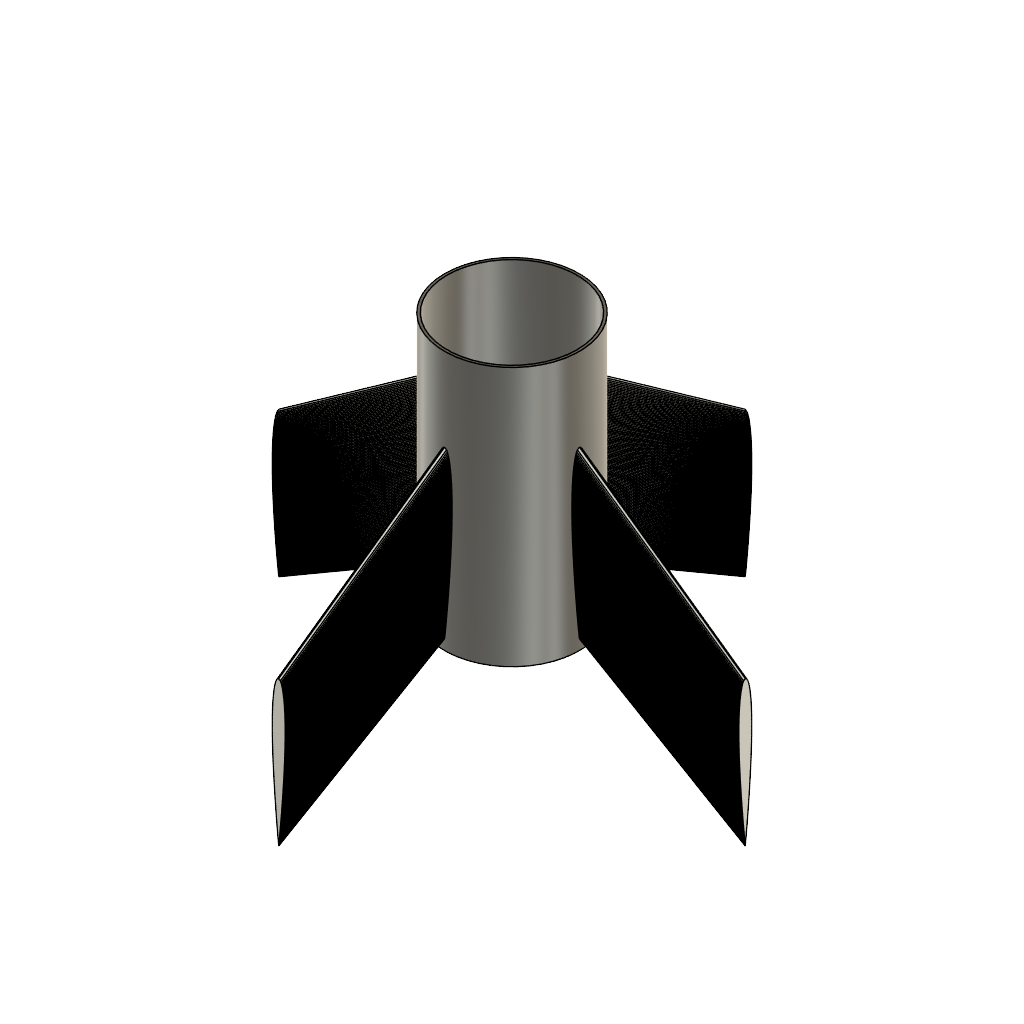
Finh canh (Autodesk Fusion 360 design; units mm, degrees)
part number: 2026-10-23-18-15-36-420
Autodesk Fusion 360 part; units mm, degrees
other "Base Mesh Feature1"
sketch "Sketch7" plane through (0, 0, 0) normal (0, 0, 1) x (1, 0, 0)
other "Modify1"
other "Modify2"
other "Modify3"
sketch "Sketch9" plane through (0, 0, 0) normal (0, 0, 1) x (1, 0, 0)
sketch "Sketch10" plane through (0, 0, 0) normal (0, 0, 1) x (1, 0, 0)
  circle A0 centre (0, 0) radius 65
  circle A1 centre (0, 0) radius 62.5
  dimension "d106" = 130
  dimension "d107" = 125
  constraint coincident A0.centre A1.centre
  measures "d106" diameter of A0
  measures "d107" diameter of A1
extrude "Extrude18" add sketch "Sketch10" along normal blind 250 makes body 1
sketch "Sketch11" plane through (0, 0, 0) normal (0, 0, 1) x (1, 0, 0)
  line L0 (0, 0) -> (140, 0) construction
  dimension "d110" = 140
  constraint coincident L0.start origin
  constraint horizontal L0
  measures "d110" distance of L0.start L0.end
sketch "Airfoil NACA 0009" plane through (0, 0, 0) normal (0, 0, 1) x (1, 0, 0)
  line L0 (140, 0) -> (138.8333, 0.1265)
  line L1 (138.8333, 0.1265) -> (137.6667, 0.2516)
  line L2 (137.6667, 0.2516) -> (136.5, 0.3755)
  line L3 (136.5, 0.3755) -> (135.3333, 0.498)
  line L4 (135.3333, 0.498) -> (134.1667, 0.6192)
  line L5 (134.1667, 0.6192) -> (133, 0.7391)
  line L6 (133, 0.7391) -> (131.8333, 0.8578)
  line L7 (131.8333, 0.8578) -> (130.6667, 0.9753)
  line L8 (130.6667, 0.9753) -> (129.5, 1.0916)
  line L9 (129.5, 1.0916) -> (128.3333, 1.2067)
  line L10 (128.3333, 1.2067) -> (127.1667, 1.3206)
  line L11 (127.1667, 1.3206) -> (126, 1.4333)
  line L12 (126, 1.4333) -> (124.8333, 1.5449)
  line L13 (124.8333, 1.5449) -> (123.6667, 1.6554)
  line L14 (123.6667, 1.6554) -> (122.5, 1.7647)
  line L15 (122.5, 1.7647) -> (121.3333, 1.8729)
  line L16 (121.3333, 1.8729) -> (120.1667, 1.9801)
  line L17 (120.1667, 1.9801) -> (119, 2.0861)
  line L18 (119, 2.0861) -> (117.8333, 2.1911)
  line L19 (117.8333, 2.1911) -> (116.6667, 2.295)
  line L20 (116.6667, 2.295) -> (115.5, 2.3979)
  line L21 (115.5, 2.3979) -> (114.3333, 2.4996)
  line L22 (114.3333, 2.4996) -> (113.1667, 2.6004)
  line L23 (113.1667, 2.6004) -> (112, 2.7001)
  line L24 (112, 2.7001) -> (110.8333, 2.7987)
  line L25 (110.8333, 2.7987) -> (109.6667, 2.8964)
  line L26 (109.6667, 2.8964) -> (108.5, 2.9929)
  line L27 (108.5, 2.9929) -> (107.3333, 3.0885)
  line L28 (107.3333, 3.0885) -> (106.1667, 3.183)
  line L29 (106.1667, 3.183) -> (105, 3.2765)
  line L30 (105, 3.2765) -> (103.8333, 3.3689)
  line L31 (103.8333, 3.3689) -> (102.6667, 3.4603)
  line L32 (102.6667, 3.4603) -> (101.5, 3.5506)
  line L33 (101.5, 3.5506) -> (100.3333, 3.6399)
  line L34 (100.3333, 3.6399) -> (99.1667, 3.7282)
  line L35 (99.1667, 3.7282) -> (98, 3.8153)
  line L36 (98, 3.8153) -> (96.8333, 3.9014)
  line L37 (96.8333, 3.9014) -> (95.6667, 3.9865)
  line L38 (95.6667, 3.9865) -> (94.5, 4.0704)
  line L39 (94.5, 4.0704) -> (93.3333, 4.1532)
  line L40 (93.3333, 4.1532) -> (92.1667, 4.2349)
  line L41 (92.1667, 4.2349) -> (91, 4.3155)
  line L42 (91, 4.3155) -> (89.8333, 4.3949)
  line L43 (89.8333, 4.3949) -> (88.6667, 4.4732)
  line L44 (88.6667, 4.4732) -> (87.5, 4.5503)
  line L45 (87.5, 4.5503) -> (86.3333, 4.6262)
  line L46 (86.3333, 4.6262) -> (85.1667, 4.7009)
  line L47 (85.1667, 4.7009) -> (84, 4.7744)
  line L48 (84, 4.7744) -> (82.8333, 4.8466)
  line L49 (82.8333, 4.8466) -> (81.6667, 4.9175)
  line L50 (81.6667, 4.9175) -> (80.5, 4.9871)
  line L51 (80.5, 4.9871) -> (79.3333, 5.0554)
  line L52 (79.3333, 5.0554) -> (78.1667, 5.1224)
  line L53 (78.1667, 5.1224) -> (77, 5.1879)
  line L54 (77, 5.1879) -> (75.8333, 5.2521)
  line L55 (75.8333, 5.2521) -> (74.6667, 5.3148)
  line L56 (74.6667, 5.3148) -> (73.5, 5.376)
  line L57 (73.5, 5.376) -> (72.3333, 5.4357)
  line L58 (72.3333, 5.4357) -> (71.1667, 5.4939)
  line L59 (71.1667, 5.4939) -> (70, 5.5505)
  line L60 (70, 5.5505) -> (68.8333, 5.6054)
  line L61 (68.8333, 5.6054) -> (67.6667, 5.6587)
  line L62 (67.6667, 5.6587) -> (66.5, 5.7103)
  line L63 (66.5, 5.7103) -> (65.3333, 5.7601)
  line L64 (65.3333, 5.7601) -> (64.1667, 5.8082)
  line L65 (64.1667, 5.8082) -> (63, 5.8543)
  line L66 (63, 5.8543) -> (61.8333, 5.8986)
  line L67 (61.8333, 5.8986) -> (60.6667, 5.941)
  line L68 (60.6667, 5.941) -> (59.5, 5.9813)
  line L69 (59.5, 5.9813) -> (58.3333, 6.0196)
  line L70 (58.3333, 6.0196) -> (57.1667, 6.0558)
  line L71 (57.1667, 6.0558) -> (56, 6.0898)
  line L72 (56, 6.0898) -> (54.8333, 6.1215)
  line L73 (54.8333, 6.1215) -> (53.6667, 6.1509)
  line L74 (53.6667, 6.1509) -> (52.5, 6.178)
  line L75 (52.5, 6.178) -> (51.3333, 6.2026)
  line L76 (51.3333, 6.2026) -> (50.1667, 6.2246)
  line L77 (50.1667, 6.2246) -> (49, 6.2441)
  line L78 (49, 6.2441) -> (47.8333, 6.2608)
  line L79 (47.8333, 6.2608) -> (46.6667, 6.2748)
  line L80 (46.6667, 6.2748) -> (45.5, 6.2858)
  line L81 (45.5, 6.2858) -> (44.3333, 6.2939)
  line L82 (44.3333, 6.2939) -> (43.1667, 6.2989)
  line L83 (43.1667, 6.2989) -> (42, 6.3007)
  line L84 (42, 6.3007) -> (40.8333, 6.2993)
  line L85 (40.8333, 6.2993) -> (39.6667, 6.2943)
  line L86 (39.6667, 6.2943) -> (38.5, 6.2859)
  line L87 (38.5, 6.2859) -> (37.3333, 6.2737)
  line L88 (37.3333, 6.2737) -> (36.1667, 6.2578)
  line L89 (36.1667, 6.2578) -> (35, 6.2378)
  line L90 (35, 6.2378) -> (33.8333, 6.2137)
  line L91 (33.8333, 6.2137) -> (32.6667, 6.1852)
  line L92 (32.6667, 6.1852) -> (31.5, 6.1523)
  line L93 (31.5, 6.1523) -> (30.3333, 6.1146)
  line L94 (30.3333, 6.1146) -> (29.1667, 6.072)
  line L95 (29.1667, 6.072) -> (28, 6.0242)
  line L96 (28, 6.0242) -> (26.8333, 5.971)
  line L97 (26.8333, 5.971) -> (25.6667, 5.9121)
  line L98 (25.6667, 5.9121) -> (24.5, 5.8471)
  line L99 (24.5, 5.8471) -> (23.3333, 5.7757)
  line L100 (23.3333, 5.7757) -> (22.1667, 5.6976)
  line L101 (22.1667, 5.6976) -> (21, 5.6124)
  line L102 (21, 5.6124) -> (19.8333, 5.5194)
  line L103 (19.8333, 5.5194) -> (18.6667, 5.4182)
  line L104 (18.6667, 5.4182) -> (17.5, 5.3081)
  line L105 (17.5, 5.3081) -> (16.3333, 5.1885)
  line L106 (16.3333, 5.1885) -> (15.1667, 5.0584)
  line L107 (15.1667, 5.0584) -> (14, 4.9169)
  line L108 (14, 4.9169) -> (12.8333, 4.7627)
  line L109 (12.8333, 4.7627) -> (11.6667, 4.5943)
  line L110 (11.6667, 4.5943) -> (10.5, 4.4099)
  line L111 (10.5, 4.4099) -> (9.3333, 4.2071)
  line L112 (9.3333, 4.2071) -> (8.1667, 3.9827)
  line L113 (8.1667, 3.9827) -> (7, 3.7324)
  line L114 (7, 3.7324) -> (5.8333, 3.4502)
  line L115 (5.8333, 3.4502) -> (4.6667, 3.1264)
  line L116 (4.6667, 3.1264) -> (3.5, 2.7455)
  line L117 (3.5, 2.7455) -> (2.3333, 2.2764)
  line L118 (2.3333, 2.2764) -> (1.1667, 1.6398)
  line L119 (1.1667, 1.6398) -> (0, 0)
  line L120 (0, 0) -> (1.1667, -1.6398)
  line L121 (1.1667, -1.6398) -> (2.3333, -2.2764)
  line L122 (2.3333, -2.2764) -> (3.5, -2.7455)
  line L123 (3.5, -2.7455) -> (4.6667, -3.1264)
  line L124 (4.6667, -3.1264) -> (5.8333, -3.4502)
  line L125 (5.8333, -3.4502) -> (7, -3.7324)
  line L126 (7, -3.7324) -> (8.1667, -3.9827)
  line L127 (8.1667, -3.9827) -> (9.3333, -4.2071)
  line L128 (9.3333, -4.2071) -> (10.5, -4.4099)
  line L129 (10.5, -4.4099) -> (11.6667, -4.5943)
  line L130 (11.6667, -4.5943) -> (12.8333, -4.7627)
  line L131 (12.8333, -4.7627) -> (14, -4.9169)
  line L132 (14, -4.9169) -> (15.1667, -5.0584)
  line L133 (15.1667, -5.0584) -> (16.3333, -5.1885)
  line L134 (16.3333, -5.1885) -> (17.5, -5.3081)
  line L135 (17.5, -5.3081) -> (18.6667, -5.4182)
  line L136 (18.6667, -5.4182) -> (19.8333, -5.5194)
  line L137 (19.8333, -5.5194) -> (21, -5.6124)
  line L138 (21, -5.6124) -> (22.1667, -5.6976)
  line L139 (22.1667, -5.6976) -> (23.3333, -5.7757)
  line L140 (23.3333, -5.7757) -> (24.5, -5.8471)
  line L141 (24.5, -5.8471) -> (25.6667, -5.9121)
  line L142 (25.6667, -5.9121) -> (26.8333, -5.971)
  line L143 (26.8333, -5.971) -> (28, -6.0242)
  line L144 (28, -6.0242) -> (29.1667, -6.072)
  line L145 (29.1667, -6.072) -> (30.3333, -6.1146)
  line L146 (30.3333, -6.1146) -> (31.5, -6.1523)
  line L147 (31.5, -6.1523) -> (32.6667, -6.1852)
  line L148 (32.6667, -6.1852) -> (33.8333, -6.2137)
  line L149 (33.8333, -6.2137) -> (35, -6.2378)
  line L150 (35, -6.2378) -> (36.1667, -6.2578)
  line L151 (36.1667, -6.2578) -> (37.3333, -6.2737)
  line L152 (37.3333, -6.2737) -> (38.5, -6.2859)
  line L153 (38.5, -6.2859) -> (39.6667, -6.2943)
  line L154 (39.6667, -6.2943) -> (40.8333, -6.2993)
  line L155 (40.8333, -6.2993) -> (42, -6.3007)
  line L156 (42, -6.3007) -> (43.1667, -6.2989)
  line L157 (43.1667, -6.2989) -> (44.3333, -6.2939)
  line L158 (44.3333, -6.2939) -> (45.5, -6.2858)
  line L159 (45.5, -6.2858) -> (46.6667, -6.2748)
  line L160 (46.6667, -6.2748) -> (47.8333, -6.2608)
  line L161 (47.8333, -6.2608) -> (49, -6.2441)
  line L162 (49, -6.2441) -> (50.1667, -6.2246)
  line L163 (50.1667, -6.2246) -> (51.3333, -6.2026)
  line L164 (51.3333, -6.2026) -> (52.5, -6.178)
  line L165 (52.5, -6.178) -> (53.6667, -6.1509)
  line L166 (53.6667, -6.1509) -> (54.8333, -6.1215)
  line L167 (54.8333, -6.1215) -> (56, -6.0898)
  line L168 (56, -6.0898) -> (57.1667, -6.0558)
  line L169 (57.1667, -6.0558) -> (58.3333, -6.0196)
  line L170 (58.3333, -6.0196) -> (59.5, -5.9813)
  line L171 (59.5, -5.9813) -> (60.6667, -5.941)
  line L172 (60.6667, -5.941) -> (61.8333, -5.8986)
  line L173 (61.8333, -5.8986) -> (63, -5.8543)
  line L174 (63, -5.8543) -> (64.1667, -5.8082)
  line L175 (64.1667, -5.8082) -> (65.3333, -5.7601)
  line L176 (65.3333, -5.7601) -> (66.5, -5.7103)
  line L177 (66.5, -5.7103) -> (67.6667, -5.6587)
  line L178 (67.6667, -5.6587) -> (68.8333, -5.6054)
  line L179 (68.8333, -5.6054) -> (70, -5.5505)
  line L180 (70, -5.5505) -> (71.1667, -5.4939)
  line L181 (71.1667, -5.4939) -> (72.3333, -5.4357)
  line L182 (72.3333, -5.4357) -> (73.5, -5.376)
  line L183 (73.5, -5.376) -> (74.6667, -5.3148)
  line L184 (74.6667, -5.3148) -> (75.8333, -5.2521)
  line L185 (75.8333, -5.2521) -> (77, -5.1879)
  line L186 (77, -5.1879) -> (78.1667, -5.1224)
  line L187 (78.1667, -5.1224) -> (79.3333, -5.0554)
  line L188 (79.3333, -5.0554) -> (80.5, -4.9871)
  line L189 (80.5, -4.9871) -> (81.6667, -4.9175)
  line L190 (81.6667, -4.9175) -> (82.8333, -4.8466)
  line L191 (82.8333, -4.8466) -> (84, -4.7744)
  line L192 (84, -4.7744) -> (85.1667, -4.7009)
  line L193 (85.1667, -4.7009) -> (86.3333, -4.6262)
  line L194 (86.3333, -4.6262) -> (87.5, -4.5503)
  line L195 (87.5, -4.5503) -> (88.6667, -4.4732)
  line L196 (88.6667, -4.4732) -> (89.8333, -4.3949)
  line L197 (89.8333, -4.3949) -> (91, -4.3155)
  line L198 (91, -4.3155) -> (92.1667, -4.2349)
  line L199 (92.1667, -4.2349) -> (93.3333, -4.1532)
  line L200 (93.3333, -4.1532) -> (94.5, -4.0704)
  line L201 (94.5, -4.0704) -> (95.6667, -3.9865)
  line L202 (95.6667, -3.9865) -> (96.8333, -3.9014)
  line L203 (96.8333, -3.9014) -> (98, -3.8153)
  line L204 (98, -3.8153) -> (99.1667, -3.7282)
  line L205 (99.1667, -3.7282) -> (100.3333, -3.6399)
  line L206 (100.3333, -3.6399) -> (101.5, -3.5506)
  line L207 (101.5, -3.5506) -> (102.6667, -3.4603)
  line L208 (102.6667, -3.4603) -> (103.8333, -3.3689)
  line L209 (103.8333, -3.3689) -> (105, -3.2765)
  line L210 (105, -3.2765) -> (106.1667, -3.183)
  line L211 (106.1667, -3.183) -> (107.3333, -3.0885)
  line L212 (107.3333, -3.0885) -> (108.5, -2.9929)
  line L213 (108.5, -2.9929) -> (109.6667, -2.8964)
  line L214 (109.6667, -2.8964) -> (110.8333, -2.7987)
  line L215 (110.8333, -2.7987) -> (112, -2.7001)
  line L216 (112, -2.7001) -> (113.1667, -2.6004)
  line L217 (113.1667, -2.6004) -> (114.3333, -2.4996)
  line L218 (114.3333, -2.4996) -> (115.5, -2.3979)
  line L219 (115.5, -2.3979) -> (116.6667, -2.295)
  line L220 (116.6667, -2.295) -> (117.8333, -2.1911)
  line L221 (117.8333, -2.1911) -> (119, -2.0861)
  line L222 (119, -2.0861) -> (120.1667, -1.9801)
  line L223 (120.1667, -1.9801) -> (121.3333, -1.8729)
  line L224 (121.3333, -1.8729) -> (122.5, -1.7647)
  line L225 (122.5, -1.7647) -> (123.6667, -1.6554)
  line L226 (123.6667, -1.6554) -> (124.8333, -1.5449)
  line L227 (124.8333, -1.5449) -> (126, -1.4333)
  line L228 (126, -1.4333) -> (127.1667, -1.3206)
  line L229 (127.1667, -1.3206) -> (128.3333, -1.2067)
  line L230 (128.3333, -1.2067) -> (129.5, -1.0916)
  line L231 (129.5, -1.0916) -> (130.6667, -0.9753)
  line L232 (130.6667, -0.9753) -> (131.8333, -0.8578)
  line L233 (131.8333, -0.8578) -> (133, -0.7391)
  line L234 (133, -0.7391) -> (134.1667, -0.6192)
  line L235 (134.1667, -0.6192) -> (135.3333, -0.498)
  line L236 (135.3333, -0.498) -> (136.5, -0.3755)
  line L237 (136.5, -0.3755) -> (137.6667, -0.2516)
  line L238 (137.6667, -0.2516) -> (138.8333, -0.1265)
  line L239 (138.8333, -0.1265) -> (140, 0)
  line L240 (140, 0) -> (140, 0)
scale "Scale1" [no effect]
ref_plane "WorkPlane3" through (70, 0, 160) normal (0, 0, 1) x (1, 0, 0)
sketch "Airfoil NACA 0009 (1)" plane through (0, 0, 160) normal (0, 0, 1) x (1, 0, 0)
  line L0 (46.72, 0) -> (45.3867, 0.1446)
  line L1 (45.3867, 0.1446) -> (44.0533, 0.2876)
  line L2 (44.0533, 0.2876) -> (42.72, 0.4291)
  line L3 (42.72, 0.4291) -> (41.3867, 0.5691)
  line L4 (41.3867, 0.5691) -> (40.0533, 0.7076)
  line L5 (40.0533, 0.7076) -> (38.72, 0.8447)
  line L6 (38.72, 0.8447) -> (37.3867, 0.9804)
  line L7 (37.3867, 0.9804) -> (36.0533, 1.1146)
  line L8 (36.0533, 1.1146) -> (34.72, 1.2475)
  line L9 (34.72, 1.2475) -> (33.3867, 1.379)
  line L10 (33.3867, 1.379) -> (32.0533, 1.5092)
  line L11 (32.0533, 1.5092) -> (30.72, 1.6381)
  line L12 (30.72, 1.6381) -> (29.3867, 1.7656)
  line L13 (29.3867, 1.7656) -> (28.0533, 1.8918)
  line L14 (28.0533, 1.8918) -> (26.72, 2.0168)
  line L15 (26.72, 2.0168) -> (25.3867, 2.1405)
  line L16 (25.3867, 2.1405) -> (24.0533, 2.2629)
  line L17 (24.0533, 2.2629) -> (22.72, 2.3841)
  line L18 (22.72, 2.3841) -> (21.3867, 2.5041)
  line L19 (21.3867, 2.5041) -> (20.0533, 2.6229)
  line L20 (20.0533, 2.6229) -> (18.72, 2.7404)
  line L21 (18.72, 2.7404) -> (17.3867, 2.8567)
  line L22 (17.3867, 2.8567) -> (16.0533, 2.9719)
  line L23 (16.0533, 2.9719) -> (14.72, 3.0858)
  line L24 (14.72, 3.0858) -> (13.3867, 3.1986)
  line L25 (13.3867, 3.1986) -> (12.0533, 3.3101)
  line L26 (12.0533, 3.3101) -> (10.72, 3.4205)
  line L27 (10.72, 3.4205) -> (9.3867, 3.5297)
  line L28 (9.3867, 3.5297) -> (8.0533, 3.6377)
  line L29 (8.0533, 3.6377) -> (6.72, 3.7445)
  line L30 (6.72, 3.7445) -> (5.3867, 3.8502)
  line L31 (5.3867, 3.8502) -> (4.0533, 3.9546)
  line L32 (4.0533, 3.9546) -> (2.72, 4.0579)
  line L33 (2.72, 4.0579) -> (1.3867, 4.1599)
  line L34 (1.3867, 4.1599) -> (0.0533, 4.2608)
  line L35 (0.0533, 4.2608) -> (-1.28, 4.3604)
  line L36 (-1.28, 4.3604) -> (-2.6133, 4.4588)
  line L37 (-2.6133, 4.4588) -> (-3.9467, 4.556)
  line L38 (-3.9467, 4.556) -> (-5.28, 4.6519)
  line L39 (-5.28, 4.6519) -> (-6.6133, 4.7465)
  line L40 (-6.6133, 4.7465) -> (-7.9467, 4.8399)
  line L41 (-7.9467, 4.8399) -> (-9.28, 4.932)
  line L42 (-9.28, 4.932) -> (-10.6133, 5.0228)
  line L43 (-10.6133, 5.0228) -> (-11.9467, 5.1123)
  line L44 (-11.9467, 5.1123) -> (-13.28, 5.2004)
  line L45 (-13.28, 5.2004) -> (-14.6133, 5.2871)
  line L46 (-14.6133, 5.2871) -> (-15.9467, 5.3725)
  line L47 (-15.9467, 5.3725) -> (-17.28, 5.4564)
  line L48 (-17.28, 5.4564) -> (-18.6133, 5.539)
  line L49 (-18.6133, 5.539) -> (-19.9467, 5.62)
  line L50 (-19.9467, 5.62) -> (-21.28, 5.6996)
  line L51 (-21.28, 5.6996) -> (-22.6133, 5.7777)
  line L52 (-22.6133, 5.7777) -> (-23.9467, 5.8542)
  line L53 (-23.9467, 5.8542) -> (-25.28, 5.9291)
  line L54 (-25.28, 5.9291) -> (-26.6133, 6.0024)
  line L55 (-26.6133, 6.0024) -> (-27.9467, 6.074)
  line L56 (-27.9467, 6.074) -> (-29.28, 6.144)
  line L57 (-29.28, 6.144) -> (-30.6133, 6.2122)
  line L58 (-30.6133, 6.2122) -> (-31.9467, 6.2787)
  line L59 (-31.9467, 6.2787) -> (-33.28, 6.3434)
  line L60 (-33.28, 6.3434) -> (-34.6133, 6.4062)
  line L61 (-34.6133, 6.4062) -> (-35.9467, 6.4671)
  line L62 (-35.9467, 6.4671) -> (-37.28, 6.526)
  line L63 (-37.28, 6.526) -> (-38.6133, 6.583)
  line L64 (-38.6133, 6.583) -> (-39.9467, 6.6379)
  line L65 (-39.9467, 6.6379) -> (-41.28, 6.6907)
  line L66 (-41.28, 6.6907) -> (-42.6133, 6.7413)
  line L67 (-42.6133, 6.7413) -> (-43.9467, 6.7897)
  line L68 (-43.9467, 6.7897) -> (-45.28, 6.8358)
  line L69 (-45.28, 6.8358) -> (-46.6133, 6.8796)
  line L70 (-46.6133, 6.8796) -> (-47.9467, 6.9209)
  line L71 (-47.9467, 6.9209) -> (-49.28, 6.9597)
  line L72 (-49.28, 6.9597) -> (-50.6133, 6.996)
  line L73 (-50.6133, 6.996) -> (-51.9467, 7.0296)
  line L74 (-51.9467, 7.0296) -> (-53.28, 7.0606)
  line L75 (-53.28, 7.0606) -> (-54.6133, 7.0887)
  line L76 (-54.6133, 7.0887) -> (-55.9467, 7.1139)
  line L77 (-55.9467, 7.1139) -> (-57.28, 7.1361)
  line L78 (-57.28, 7.1361) -> (-58.6133, 7.1552)
  line L79 (-58.6133, 7.1552) -> (-59.9467, 7.1711)
  line L80 (-59.9467, 7.1711) -> (-61.28, 7.1838)
  line L81 (-61.28, 7.1838) -> (-62.6133, 7.193)
  line L82 (-62.6133, 7.193) -> (-63.9467, 7.1988)
  line L83 (-63.9467, 7.1988) -> (-65.28, 7.2008)
  line L84 (-65.28, 7.2008) -> (-66.6133, 7.1992)
  line L85 (-66.6133, 7.1992) -> (-67.9467, 7.1935)
  line L86 (-67.9467, 7.1935) -> (-69.28, 7.1839)
  line L87 (-69.28, 7.1839) -> (-70.6133, 7.17)
  line L88 (-70.6133, 7.17) -> (-71.9467, 7.1517)
  line L89 (-71.9467, 7.1517) -> (-73.28, 7.1289)
  line L90 (-73.28, 7.1289) -> (-74.6133, 7.1013)
  line L91 (-74.6133, 7.1013) -> (-75.9467, 7.0688)
  line L92 (-75.9467, 7.0688) -> (-77.28, 7.0312)
  line L93 (-77.28, 7.0312) -> (-78.6133, 6.9881)
  line L94 (-78.6133, 6.9881) -> (-79.9467, 6.9394)
  line L95 (-79.9467, 6.9394) -> (-81.28, 6.8848)
  line L96 (-81.28, 6.8848) -> (-82.6133, 6.824)
  line L97 (-82.6133, 6.824) -> (-83.9467, 6.7566)
  line L98 (-83.9467, 6.7566) -> (-85.28, 6.6824)
  line L99 (-85.28, 6.6824) -> (-86.6133, 6.6009)
  line L100 (-86.6133, 6.6009) -> (-87.9467, 6.5116)
  line L101 (-87.9467, 6.5116) -> (-89.28, 6.4141)
  line L102 (-89.28, 6.4141) -> (-90.6133, 6.3079)
  line L103 (-90.6133, 6.3079) -> (-91.9467, 6.1922)
  line L104 (-91.9467, 6.1922) -> (-93.28, 6.0664)
  line L105 (-93.28, 6.0664) -> (-94.6133, 5.9297)
  line L106 (-94.6133, 5.9297) -> (-95.9467, 5.7811)
  line L107 (-95.9467, 5.7811) -> (-97.28, 5.6193)
  line L108 (-97.28, 5.6193) -> (-98.6133, 5.4431)
  line L109 (-98.6133, 5.4431) -> (-99.9467, 5.2506)
  line L110 (-99.9467, 5.2506) -> (-101.28, 5.0399)
  line L111 (-101.28, 5.0399) -> (-102.6133, 4.8081)
  line L112 (-102.6133, 4.8081) -> (-103.9467, 4.5516)
  line L113 (-103.9467, 4.5516) -> (-105.28, 4.2656)
  line L114 (-105.28, 4.2656) -> (-106.6133, 3.943)
  line L115 (-106.6133, 3.943) -> (-107.9467, 3.5731)
  line L116 (-107.9467, 3.5731) -> (-109.28, 3.1377)
  line L117 (-109.28, 3.1377) -> (-110.6133, 2.6016)
  line L118 (-110.6133, 2.6016) -> (-111.9467, 1.8741)
  line L119 (-111.9467, 1.8741) -> (-113.28, 0)
  line L120 (-113.28, 0) -> (-111.9467, -1.8741)
  line L121 (-111.9467, -1.8741) -> (-110.6133, -2.6016)
  line L122 (-110.6133, -2.6016) -> (-109.28, -3.1377)
  line L123 (-109.28, -3.1377) -> (-107.9467, -3.5731)
  line L124 (-107.9467, -3.5731) -> (-106.6133, -3.943)
  line L125 (-106.6133, -3.943) -> (-105.28, -4.2656)
  line L126 (-105.28, -4.2656) -> (-103.9467, -4.5516)
  line L127 (-103.9467, -4.5516) -> (-102.6133, -4.8081)
  line L128 (-102.6133, -4.8081) -> (-101.28, -5.0399)
  line L129 (-101.28, -5.0399) -> (-99.9467, -5.2506)
  line L130 (-99.9467, -5.2506) -> (-98.6133, -5.4431)
  line L131 (-98.6133, -5.4431) -> (-97.28, -5.6193)
  line L132 (-97.28, -5.6193) -> (-95.9467, -5.7811)
  line L133 (-95.9467, -5.7811) -> (-94.6133, -5.9297)
  line L134 (-94.6133, -5.9297) -> (-93.28, -6.0664)
  line L135 (-93.28, -6.0664) -> (-91.9467, -6.1922)
  line L136 (-91.9467, -6.1922) -> (-90.6133, -6.3079)
  line L137 (-90.6133, -6.3079) -> (-89.28, -6.4141)
  line L138 (-89.28, -6.4141) -> (-87.9467, -6.5116)
  line L139 (-87.9467, -6.5116) -> (-86.6133, -6.6009)
  line L140 (-86.6133, -6.6009) -> (-85.28, -6.6824)
  line L141 (-85.28, -6.6824) -> (-83.9467, -6.7566)
  line L142 (-83.9467, -6.7566) -> (-82.6133, -6.824)
  line L143 (-82.6133, -6.824) -> (-81.28, -6.8848)
  line L144 (-81.28, -6.8848) -> (-79.9467, -6.9394)
  line L145 (-79.9467, -6.9394) -> (-78.6133, -6.9881)
  line L146 (-78.6133, -6.9881) -> (-77.28, -7.0312)
  line L147 (-77.28, -7.0312) -> (-75.9467, -7.0688)
  line L148 (-75.9467, -7.0688) -> (-74.6133, -7.1013)
  line L149 (-74.6133, -7.1013) -> (-73.28, -7.1289)
  line L150 (-73.28, -7.1289) -> (-71.9467, -7.1517)
  line L151 (-71.9467, -7.1517) -> (-70.6133, -7.17)
  line L152 (-70.6133, -7.17) -> (-69.28, -7.1839)
  line L153 (-69.28, -7.1839) -> (-67.9467, -7.1935)
  line L154 (-67.9467, -7.1935) -> (-66.6133, -7.1992)
  line L155 (-66.6133, -7.1992) -> (-65.28, -7.2008)
  line L156 (-65.28, -7.2008) -> (-63.9467, -7.1988)
  line L157 (-63.9467, -7.1988) -> (-62.6133, -7.193)
  line L158 (-62.6133, -7.193) -> (-61.28, -7.1838)
  line L159 (-61.28, -7.1838) -> (-59.9467, -7.1711)
  line L160 (-59.9467, -7.1711) -> (-58.6133, -7.1552)
  line L161 (-58.6133, -7.1552) -> (-57.28, -7.1361)
  line L162 (-57.28, -7.1361) -> (-55.9467, -7.1139)
  line L163 (-55.9467, -7.1139) -> (-54.6133, -7.0887)
  line L164 (-54.6133, -7.0887) -> (-53.28, -7.0606)
  line L165 (-53.28, -7.0606) -> (-51.9467, -7.0296)
  line L166 (-51.9467, -7.0296) -> (-50.6133, -6.996)
  line L167 (-50.6133, -6.996) -> (-49.28, -6.9597)
  line L168 (-49.28, -6.9597) -> (-47.9467, -6.9209)
  line L169 (-47.9467, -6.9209) -> (-46.6133, -6.8796)
  line L170 (-46.6133, -6.8796) -> (-45.28, -6.8358)
  line L171 (-45.28, -6.8358) -> (-43.9467, -6.7897)
  line L172 (-43.9467, -6.7897) -> (-42.6133, -6.7413)
  line L173 (-42.6133, -6.7413) -> (-41.28, -6.6907)
  line L174 (-41.28, -6.6907) -> (-39.9467, -6.6379)
  line L175 (-39.9467, -6.6379) -> (-38.6133, -6.583)
  line L176 (-38.6133, -6.583) -> (-37.28, -6.526)
  line L177 (-37.28, -6.526) -> (-35.9467, -6.4671)
  line L178 (-35.9467, -6.4671) -> (-34.6133, -6.4062)
  line L179 (-34.6133, -6.4062) -> (-33.28, -6.3434)
  line L180 (-33.28, -6.3434) -> (-31.9467, -6.2787)
  line L181 (-31.9467, -6.2787) -> (-30.6133, -6.2122)
  line L182 (-30.6133, -6.2122) -> (-29.28, -6.144)
  line L183 (-29.28, -6.144) -> (-27.9467, -6.074)
  line L184 (-27.9467, -6.074) -> (-26.6133, -6.0024)
  line L185 (-26.6133, -6.0024) -> (-25.28, -5.9291)
  line L186 (-25.28, -5.9291) -> (-23.9467, -5.8542)
  line L187 (-23.9467, -5.8542) -> (-22.6133, -5.7777)
  line L188 (-22.6133, -5.7777) -> (-21.28, -5.6996)
  line L189 (-21.28, -5.6996) -> (-19.9467, -5.62)
  line L190 (-19.9467, -5.62) -> (-18.6133, -5.539)
  line L191 (-18.6133, -5.539) -> (-17.28, -5.4564)
  line L192 (-17.28, -5.4564) -> (-15.9467, -5.3725)
  line L193 (-15.9467, -5.3725) -> (-14.6133, -5.2871)
  line L194 (-14.6133, -5.2871) -> (-13.28, -5.2004)
  line L195 (-13.28, -5.2004) -> (-11.9467, -5.1123)
  line L196 (-11.9467, -5.1123) -> (-10.6133, -5.0228)
  line L197 (-10.6133, -5.0228) -> (-9.28, -4.932)
  line L198 (-9.28, -4.932) -> (-7.9467, -4.8399)
  line L199 (-7.9467, -4.8399) -> (-6.6133, -4.7465)
  line L200 (-6.6133, -4.7465) -> (-5.28, -4.6519)
  line L201 (-5.28, -4.6519) -> (-3.9467, -4.556)
  line L202 (-3.9467, -4.556) -> (-2.6133, -4.4588)
  line L203 (-2.6133, -4.4588) -> (-1.28, -4.3604)
  line L204 (-1.28, -4.3604) -> (0.0533, -4.2608)
  line L205 (0.0533, -4.2608) -> (1.3867, -4.1599)
  line L206 (1.3867, -4.1599) -> (2.72, -4.0579)
  line L207 (2.72, -4.0579) -> (4.0533, -3.9546)
  line L208 (4.0533, -3.9546) -> (5.3867, -3.8502)
  line L209 (5.3867, -3.8502) -> (6.72, -3.7445)
  line L210 (6.72, -3.7445) -> (8.0533, -3.6377)
  line L211 (8.0533, -3.6377) -> (9.3867, -3.5297)
  line L212 (9.3867, -3.5297) -> (10.72, -3.4205)
  line L213 (10.72, -3.4205) -> (12.0533, -3.3101)
  line L214 (12.0533, -3.3101) -> (13.3867, -3.1986)
  line L215 (13.3867, -3.1986) -> (14.72, -3.0858)
  line L216 (14.72, -3.0858) -> (16.0533, -2.9719)
  line L217 (16.0533, -2.9719) -> (17.3867, -2.8567)
  line L218 (17.3867, -2.8567) -> (18.72, -2.7404)
  line L219 (18.72, -2.7404) -> (20.0533, -2.6229)
  line L220 (20.0533, -2.6229) -> (21.3867, -2.5041)
  line L221 (21.3867, -2.5041) -> (22.72, -2.3841)
  line L222 (22.72, -2.3841) -> (24.0533, -2.2629)
  line L223 (24.0533, -2.2629) -> (25.3867, -2.1405)
  line L224 (25.3867, -2.1405) -> (26.72, -2.0168)
  line L225 (26.72, -2.0168) -> (28.0533, -1.8918)
  line L226 (28.0533, -1.8918) -> (29.3867, -1.7656)
  line L227 (29.3867, -1.7656) -> (30.72, -1.6381)
  line L228 (30.72, -1.6381) -> (32.0533, -1.5092)
  line L229 (32.0533, -1.5092) -> (33.3867, -1.379)
  line L230 (33.3867, -1.379) -> (34.72, -1.2475)
  line L231 (34.72, -1.2475) -> (36.0533, -1.1146)
  line L232 (36.0533, -1.1146) -> (37.3867, -0.9804)
  line L233 (37.3867, -0.9804) -> (38.72, -0.8447)
  line L234 (38.72, -0.8447) -> (40.0533, -0.7076)
  line L235 (40.0533, -0.7076) -> (41.3867, -0.5691)
  line L236 (41.3867, -0.5691) -> (42.72, -0.4291)
  line L237 (42.72, -0.4291) -> (44.0533, -0.2876)
  line L238 (44.0533, -0.2876) -> (45.3867, -0.1446)
  line L239 (45.3867, -0.1446) -> (46.72, 0)
  line L240 (46.72, 0) -> (46.72, 0)
scale "Scale2" [no effect]
loft "Loft1" add profiles "Airfoil NACA 0009 (1)", "Airfoil NACA 0009" section 1 section 2 separate body makes body 2
move_body "Move6" bodies 2 to x (0, 0, -1) y (0, 1, 0) z (1, 0, 0) at (-113.28, 0, -113.28)
move_body "Move7" bodies 2 to x (1, 0, 0) y (0, 1, 0) z (0, 0, 1) at (-125, 0, 200)
ref_plane "WorkPlane4" through (-65, 0, 225.7024) normal (-1, 0, 0) x (0, 1, 0)
sketch "Sketch15" plane through (-65, 0, 0) normal (-1, 0, 0) x (0, -1, 0)
  line L0 (0, 0) -> (0, 150) construction
  dimension "d120" = 150
  constraint coincident L0.start origin
  constraint vertical L0
  measures "d120" distance of L0.start L0.end
move_body "Move8" bodies 2 to x (1, 0, 0) y (0, 1, 0) z (0, 0, 1) at (13.28, 0, -50)
move_body "Move9" bodies 2 to x (1, 0, 0) y (0, 1, 0) z (0, 0, 1) at (0, 0, 20)
pattern_circular "C-Pattern3" count 4 over 360 about axis through (0, 0, 1.75) along (0, 0, 1) of bodies 2 makes body 3 at (-2.3671, -65, 130.4444) makes body 4 at (65, -2.3671, 130.4444) makes body 5 at (2.3671, 65, 130.4444)
named bodies: "Main Can"
